Untitled (uRoxerIs) (Autodesk Fusion 360 design; units mm, degrees)
Autodesk Fusion 360 part; units mm, degrees
sketch "Sketch1" plane through (0, 0, 0) normal (0, 1, 0) x (1, 0, 0)
  circle A0 centre (0, 0) radius 26.65
  circle A1 centre (0, 0) radius 26.4
  circle A2 centre (0, 0) radius 26.15
  circle A3 centre (0, 0) radius 26.9
  dimension "d1" = 53.3
  dimension "d2" = 52.8
  dimension "d3" = 52.3
  dimension "d4" = 53.8
  constraint coincident A0.centre A1.centre
  measures "d1" diameter of A0
  measures "d2" diameter of A1
  measures "d3" diameter of A2
  measures "d4" diameter of A3
extrude "Extrude1" add sketch "Sketch1" along normal blind 15 makes body 1 at (26.2688, 10, 2.6286) makes body 2 at (26.7663, 10, 2.6784)
sketch "Sketch2" plane through (0, 15, 0) normal (0, 1, 0) x (-1, 0, 0)
  circle A0 centre (0, 0) radius 26.65
  circle A1 centre (0, 0) radius 26.9
  circle A2 centre (0, 0) radius 26.9
  constraint coincident A0.centre A1.centre
extrude "Extrude2" add sketch "Sketch2" along normal blind 2 separate body contours A0 | A1 A2 makes body 3
sketch "Sketch3" plane through (0, 15, 0) normal (0, 1, 0) x (-1, 0, 0)
  circle A0 centre (0, 0) radius 26.15
  circle A1 centre (0, 0) radius 26.4
  circle A2 centre (0, 0) radius 26.8701
  constraint concentric A0 A2
extrude "Extrude3" add sketch "Sketch3" against normal blind 2 contours A1 | A2 bodies 1 2
ref_plane "WorkPlane1" through (0, 15.5716, 26.9) normal (0, 0, 1) x (-1, 0, 0)
sketch "Sketch4" plane through (0, 15.5716, 26.9) normal (0, 0, 1) x (1, 0, 0)
  line L0 (-3, -0.5708) -> (-3, 1.4292)
  line L1 (-3, 1.4292) -> (3.2108, 1.4292)
  line L2 (-3, -0.5708) -> (3.2108, -0.5708)
  line L3 (3.2108, -0.5708) -> (3.2108, 1.4292)
  line L4 (0, 0) -> (0.1054, 0)
  line L5 (-3, -0.5708) -> (3.2108, -0.5708)
  line L6 (3.2108, -0.5708) -> (3.2108, -3.5708)
  line L7 (3.2108, -3.5708) -> (-3, -3.5708)
  line L8 (-3, -3.5708) -> (-3, -0.5708)
  line L9 (0, 0) -> (0, 1.4292)
  line L10 (0, 1.4292) -> (-0.0857, 1.4292)
  line L11 (0, 1.4292) -> (-2, 1.4292)
  line L12 (-2, 1.4292) -> (2, 1.4292)
  line L13 (2, 1.4292) -> (2, -3.5708)
  line L14 (2, -3.5708) -> (-2, -3.5708)
  line L15 (-2, -3.5708) -> (-2, 1.4292)
  line L16 (-2, 1.4292) -> (-5, 1.4292)
  line L17 (2, 1.4292) -> (5, 1.4292)
  line L18 (3.2108, -3.5708) -> (5, -3.5708)
  line L19 (-5, 1.4292) -> (5, 1.4292)
  line L20 (5, 1.4292) -> (5, -3.5708)
  line L21 (5, -3.5708) -> (-5, -3.5708)
  line L22 (-5, -3.5708) -> (-5, 1.4292)
  line L23 (-2, 1.4292) -> (2, 1.4292)
  line L24 (2, 1.4292) -> (2, -2.5708)
  line L25 (2, -2.5708) -> (-2, -2.5708)
  line L26 (-2, -2.5708) -> (-2, 1.4292)
  dimension "d25" = 4
  constraint perpendicular L0 L1
  constraint perpendicular L0 L2
  constraint perpendicular L1 L3
  constraint coincident L4.start L9.start
  constraint perpendicular L0 L4
  constraint horizontal L5
  constraint vertical L6
  constraint horizontal L7
  constraint vertical L8
  constraint coincident L1 L9.end
  constraint perpendicular L1 L9
  constraint coincident L1 L10.end
  constraint perpendicular L9 L11
  constraint horizontal L12
  constraint vertical L13
  constraint horizontal L14
  constraint vertical L15
  constraint coincident L7 L13.end
  constraint perpendicular L0 L16
  constraint perpendicular L13 L17
  constraint perpendicular L6 L18
  constraint horizontal L19
  constraint vertical L20
  constraint horizontal L21
  constraint vertical L22
  constraint horizontal L23
  constraint vertical L24
  constraint horizontal L25
  constraint vertical L26
  measures "d25" distance of L11.end L25.end
hidden bodies 1
